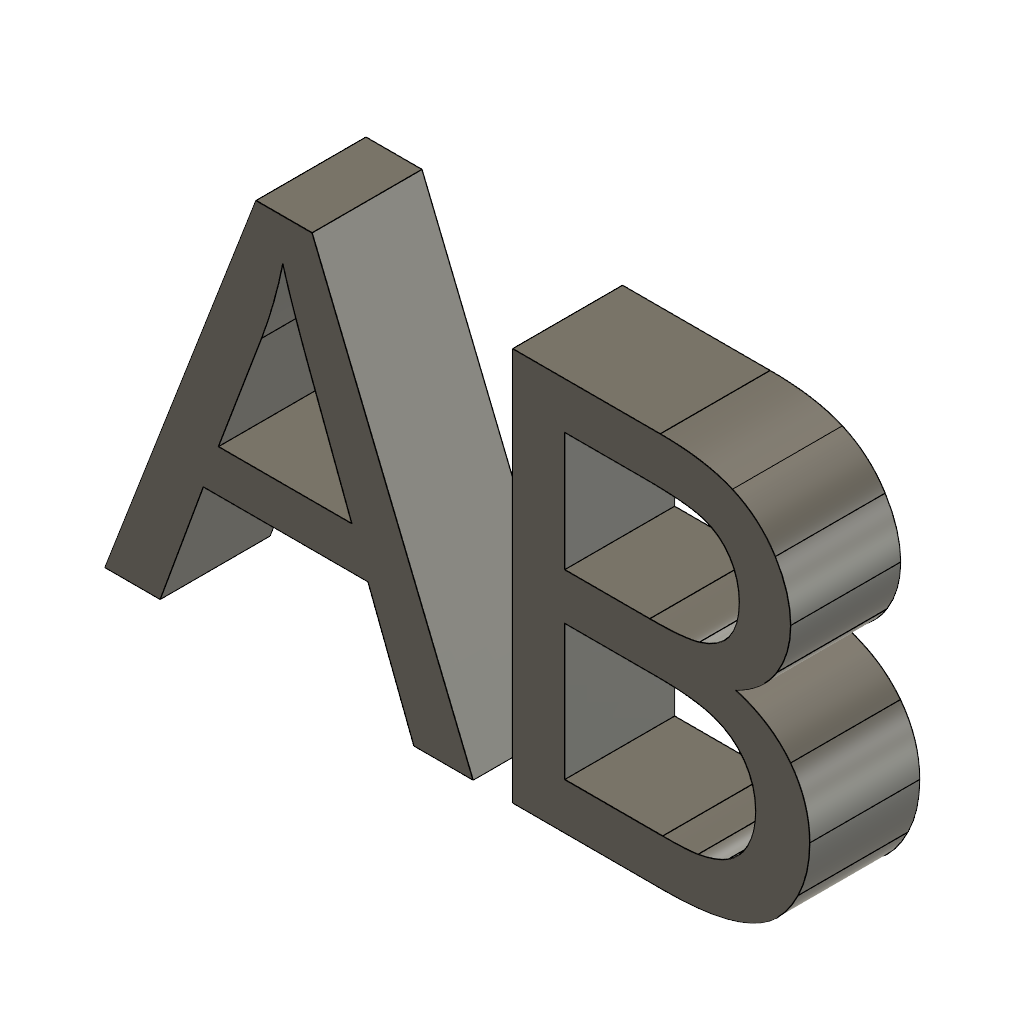
sk_text_extrude (Autodesk Fusion 360 design; units mm, degrees)
part number: 2026-11-13-14-36-51-090
Autodesk Fusion 360 part; units mm, degrees
sketch "Sketch1" plane through (0, 0, 0) normal (0, 0, 1) x (1, 0, 0)
  line L0 (0, 0) -> (12.8223, 0) construction
  line L1 (12.8223, 0) -> (12.8223, 10) construction
  line L2 (12.8223, 10) -> (0, 10) construction
  line L3 (0, 10) -> (0, 0) construction
  text T0 "AB" font "Arial" height 10 align ink ink in box 0 x 0 at (0, 0) x (1, 0) y (0, 1) spacing 1 height is em
  constraint perpendicular L0 L1
  constraint parallel L0 L2
  constraint parallel L1 L3
extrude "Extrude1" add sketch "Sketch1" along normal blind 2 text T0 makes body 1 at (7.7427, 3.508, 0) makes body 2 at (4.7561, 4.7921, 0.6667)
